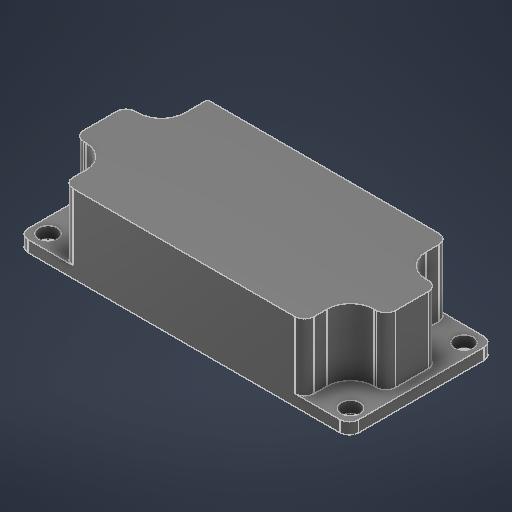
# Autodesk Inventor part: speaker
Saved by Autodesk Inventor 2027.1 (Build 311270010, 270A)
## iProperties
Created: 2026-10-18
Part Number: speaker
Material: ABS 플라스틱
Document SubType Name: Modeling
Designer: work
Density: 1.06 g/cm^3
Appearance: 매끄러움 - 검은색
Author: work
Autodesk Inventor part; units mm, degrees
ref_plane "YZ Plane" through (0, 0, 0) normal (1, 0, 0) x (0, 1, 0)
ref_plane "XZ Plane" through (0, 0, 0) normal (0, 1, 0) x (-1, 0, 0)
ref_plane "XY Plane" through (0, 0, 0) normal (0, 0, 1) x (1, 0, 0)
sketch "스케치1" plane through (0, 0, 0) normal (0, 1, 0) x (-1, 0, 0)
  line L0 (0, 0) -> (70, 0)
  line L1 (70, 0) -> (70, -30.5)
  line L2 (70, -30.5) -> (0, -30.5)
  line L3 (0, -30.5) -> (0, 0)
  line L4 (67, -3.25) -> (3, -3.25) construction
  line L5 (3, -3.25) -> (3, -27.25) construction
  line L6 (3, -27.25) -> (67, -27.25) construction
  line L7 (67, -27.25) -> (67, -3.25) construction
  circle A0 centre (67, -3.25) radius 2
  circle A1 centre (67, -27.25) radius 2
  circle A2 centre (3, -3.25) radius 2
  circle A3 centre (3, -27.25) radius 2
  line L8 (60.5, 0) -> (9.5, 0)
  line L9 (9.5, 0) -> (9.5, -30.5)
  line L10 (9.5, -30.5) -> (60.5, -30.5)
  line L11 (60.5, -30.5) -> (60.5, 0)
  line L12 (68, -20.75) -> (60.5, -20.75)
  line L13 (60.5, -20.75) -> (60.5, -9.75)
  line L14 (60.5, -9.75) -> (68, -9.75)
  line L15 (68, -9.75) -> (68, -20.75)
  line L16 (35, 0) -> (35, -30.5) construction
  line L17 (3, -27.25) -> (3, -3.25) construction
  line L18 (2, -20.75) -> (9.5, -20.75)
  line L19 (9.5, -9.75) -> (2, -9.75)
  line L20 (2, -9.75) -> (2, -20.75)
  point P0 (67, -15.25)
  point P1 (70, -15.25)
  point P2 (35, -27.25)
  point P3 (60.5, -15.25)
  point P4 (3, -15.25)
  point P5 (9.5, 0)
  dimension "d0" = 70
  dimension "d1" = 30.5
  dimension "d2" = 64
  dimension "d3" = 24
  dimension "d4" = 4
  dimension "d5" = 4
  dimension "d6" = 4
  dimension "d7" = 4
  dimension "d8" = 51
  dimension "d9" = 11
  dimension "d10" = 2
  constraints: 42 end point, 9 midpoint, 8 parallel, 5 perpendicular, 5 symmetric about line, 4 centre point, 4 coincident, 4 horizontal, 1 horizontal alignment, 1 vertical alignment
  measures "d0" distance of L1.end L2.end
  measures "d1" distance of L0.end L1.end
  measures "d2" distance of L5.end L6.end
  measures "d3" distance of L6.end L4.start
  measures "d4" diameter of A0
  measures "d5" diameter of A1
  measures "d6" diameter of A2
  measures "d7" diameter of A3
  measures "d8" distance of L9.end L10.end
  measures "d9" distance of L14.end L12.start
  measures "d10" distance between parallel lines of L15 L1
extrude "돌출1" add sketch "스케치1" along normal blind 2.4 contours L0 L9 L19 L20 L18 L2 L3 | L0 L1 L2 L11 L12 L15 L14
extrude "돌출2" add sketch "스케치1" along normal blind 16.5 contours L0 L11 L2 L9 | L9 L18 L20 L19 | L14 L15 L12 L11
fillet "모깎기1" radius 5 4 edges at (-9.5, 9.45, -9.75) (-9.5, 9.45, -20.75) (-60.5, 9.45, -9.75) (-60.5, 9.45, -20.75)
fillet "모깎기2" radius 2 11 edges at (-68, 9.45, -9.75) (-68, 9.45, -20.75) (-70, 1.2, -30.5) (-70, 1.2, 0) (-60.5, 9.45, 0) (-9.5, 9.45, 0) (-2, 9.45, -9.75) (-2, 9.45, -20.75) (-9.5, 9.45, -30.5) (0, 1.2, -30.5) (0, 1.2, 0)
